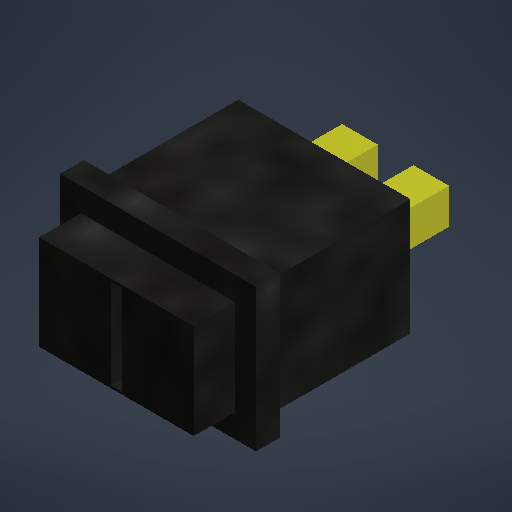
# Autodesk Inventor part: Side_Power_Switch
Saved by Autodesk Inventor 2027.1 (Build 311270010, 270A)
## iProperties
Part Number: Side_Power_Switch
Material: Generic
Document SubType Name: Modeling
Designer: austin
Appearance: Smooth - Black
Author: austin
Autodesk Inventor part; units mm, degrees
sketch "Sketch1" plane through (0, 0, 0) normal (0, 0, 1) x (1, 0, 0)
  line L0 (-8.25, -6) -> (8.25, -6)
  line L1 (8.25, -6) -> (8.25, 6)
  line L2 (8.25, 6) -> (-8.25, 6)
  line L3 (-8.25, 6) -> (-8.25, -6)
  constraints: 8 end point, 2 parallel, 1 horizontal, 1 perpendicular
extrude "Extrusion1" add sketch "Sketch1" along normal blind 2
sketch "Sketch2" plane through (0, 0, 0) normal (0, 0, 1) x (1, 0, 0)
  line L0 (-7.25, -4.9) -> (7.25, -4.9)
  line L1 (7.25, -4.9) -> (7.25, 4.9)
  line L2 (7.25, 4.9) -> (-7.25, 4.9)
  line L3 (-7.25, 4.9) -> (-7.25, -4.9)
  constraints: 8 end point, 2 parallel, 1 horizontal, 1 perpendicular
extrude "Extrusion2" add sketch "Sketch2" against normal blind 12
ref_plane "Work Plane1" through (0, 0, 2) normal (0, 0, 1) x (1, 0, 0)
sketch "Sketch3" plane through (0, 0, 2) normal (0, 0, 1) x (1, 0, 0)
  line L0 (-6.5, -4) -> (6.5, -4)
  line L1 (6.5, -4) -> (6.5, 4)
  line L2 (6.5, 4) -> (-6.5, 4)
  line L3 (-6.5, 4) -> (-6.5, -4)
  constraints: 8 end point, 2 parallel, 1 horizontal, 1 perpendicular
extrude "Extrusion3" add sketch "Sketch3" along normal blind 3.5
ref_plane "Work Plane2" through (0, 0, 5.5) normal (0, 0, 1) x (1, 0, 0)
sketch "Sketch4" plane through (0, 0, 5.5) normal (0, 0, 1) x (1, 0, 0)
  line L0 (-0.5, -3.8) -> (0.5, -3.8)
  line L1 (0.5, -3.8) -> (0.5, 3.8)
  line L2 (0.5, 3.8) -> (-0.5, 3.8)
  line L3 (-0.5, 3.8) -> (-0.5, -3.8)
  constraints: 8 end point, 2 parallel, 1 horizontal, 1 perpendicular
extrude "Extrusion4" cut sketch "Sketch4" against normal blind 1
ref_plane "Work Plane3" through (0, 0, -12) normal (0, 0, 1) x (1, 0, 0)
sketch "Sketch5" plane through (0, 0, -12) normal (0, 0, 1) x (1, 0, 0)
  line L0 (-4.5, -1.5) -> (-1.5, -1.5)
  line L1 (-1.5, -1.5) -> (-1.5, 1.5)
  line L2 (-1.5, 1.5) -> (-4.5, 1.5)
  line L3 (-4.5, 1.5) -> (-4.5, -1.5)
  line L4 (1.5, -1.5) -> (4.5, -1.5)
  line L5 (4.5, -1.5) -> (4.5, 1.5)
  line L6 (4.5, 1.5) -> (1.5, 1.5)
  line L7 (1.5, 1.5) -> (1.5, -1.5)
  constraints: 16 end point, 4 parallel, 2 horizontal, 2 perpendicular
extrude "Extrusion5" add sketch "Sketch5" against normal blind 6
body "Solid1"
